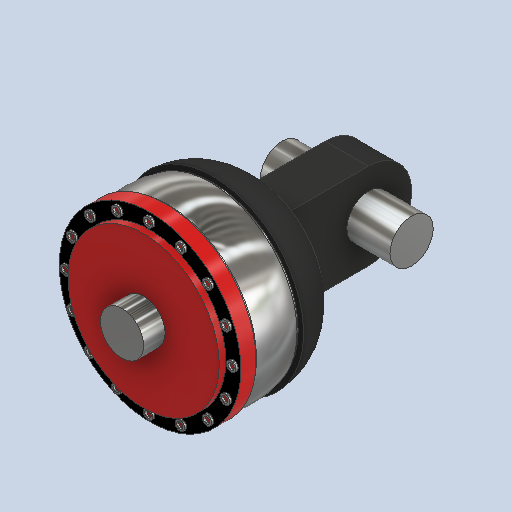
# Autodesk Inventor part: 6
Saved by Autodesk Inventor 2027.1 (Build 311270010, 270A)
## iProperties
Part Number: 6
Material: Allgemein
Document SubType Name: Modellieren
Designer: Asus
Appearance: Chrom - poliert
Author: Asus
Autodesk Inventor part; units mm, degrees
ref_plane "YZ-Ebene" through (0, 0, 0) normal (1, 0, 0) x (0, 1, 0)
ref_plane "XZ-Ebene" through (0, 0, 0) normal (0, 1, 0) x (-1, 0, 0)
sketch "Skizze1" plane through (0, 0, 0) normal (0, 0, 1) x (1, 0, 0)
  line L0 (0, 0) -> (20, 0)
  line L1 (0, 0) -> (0, -42)
  line L2 (20, 0) -> (20, -31)
  arc A0 (0, -42) -> (20, -31) centre (-0.7193, -17.0104) ccw
  dimension "d0" = 20
  dimension "d1" = 42
  dimension "d2" = 31
  dimension "d3" = 25
  constraints: 6 end point, 2 point on circle, 2 vertical, 1 centre point, 1 horizontal
  measures "d0" distance of L0.start L0.end
  measures "d1" distance of L0.start L1.end
  measures "d2" distance of L0.end L2.end
  measures "d3" radius of A0
revolve "Umdrehung1" add sketch "Skizze1" angle 360 about axis through (0, 0, 0) along (1, 0, 0)
sketch "Skizze2" plane through (0, 0, 0) normal (-1, 0, 0) x (0, 0, 1)
  circle A0 centre (0, 0) radius 39.5
  dimension "d5" = 79
  constraints: 1 centre point, 1 coincident
  measures "d5" diameter of A0
extrude "Extrusion1" add sketch "Skizze2" along normal blind 1
sketch "Skizze3" plane through (0, 0, 0) normal (0, 1, 0) x (-1, 0, 0)
  line L0 (1, -39.5) -> (0, -39.5) construction
  line L1 (0, -39.5) -> (0, -42) construction
  arc A0 (-20, -31) -> (0, -42) centre (0.7193, -17.0104) ccw construction
  line L2 (-20, -31) -> (-20, 31) construction
  arc A1 (0, 42) -> (-20, 31) centre (0.7193, 17.0104) ccw construction
  line L3 (0, 42) -> (0, 39.5) construction
  line L4 (0, 39.5) -> (1, 39.5) construction
  line L5 (1, 39.5) -> (1, -39.5) construction
  line L6 (1, 0) -> (21, 0)
  line L7 (1, 0) -> (1, 40)
  line L8 (21, 0) -> (21, 40)
  arc A2 (21, 40) -> (1, 40) centre (11, 4.377) ccw
  point P0 (0, 0)
  dimension "d8" = 20
  dimension "d9" = 40
  dimension "d10" = 40
  dimension "d11" = 37
  constraints: 6 end point, 2 point on circle, 1 centre point, 1 horizontal, 1 midpoint, 1 point on line, 1 vertical
  measures "d8" distance of L6.start L6.end
  measures "d9" distance of L6.start L7.end
  measures "d10" distance of L6.end L8.end
  measures "d11" radius of A2
revolve "Umdrehung2" add sketch "Skizze3" angle 360 about axis through (-1, 0, 0) along (-1, 0, 0)
sketch "Skizze4" plane through (-21, 0, 0) normal (-1, 0, 0) x (0, 0, 1)
  circle A0 centre (0, 0) radius 41.25
  dimension "d13" = 82.5
  constraints: 1 centre point, 1 coincident
  measures "d13" diameter of A0
extrude "Extrusion2" add sketch "Skizze4" along normal blind 1
sketch "Skizze5" plane through (-22, 0, 0) normal (-1, 0, 0) x (0, 0, 1)
  circle A0 centre (0, 0) radius 42
  dimension "d16" = 84
  constraints: 1 centre point, 1 coincident
  measures "d16" diameter of A0
extrude "Extrusion3" add sketch "Skizze5" along normal blind 7
sketch "Skizze6" plane through (-29, 0, 0) normal (-1, 0, 0) x (0, 0, 1)
  circle A0 centre (0, 0) radius 35
  dimension "d19" = 70
  constraints: 1 centre point, 1 coincident
  measures "d19" diameter of A0
extrude "Extrusion4" add sketch "Skizze6" along normal blind 3
sketch "Skizze7" plane through (-29, 0, 0) normal (-1, 0, 0) x (0, 0, 1)
  circle A0 centre (0, 0) radius 35 construction
  circle A1 centre (0, 0) radius 42 construction
  circle A2 centre (-38.5, 0) radius 2.25
  circle A3 centre (-38.5, 0) radius 1.5
  dimension "d22" = 4.5
  dimension "d23" = 3
  dimension "d24" = 38.5
  constraints: 2 centre point, 1 coincident, 1 horizontal alignment
  measures "d22" diameter of A2
  measures "d23" diameter of A3
  measures "d24" distance of point (0, 0) A2.centre
extrude "Extrusion5" add sketch "Skizze7" along normal blind 1
pattern_circular "Runde Anordnung1" count 16 over 360 about axis through (-29, 0, 0) along (-1, 0, 0) of "Extrusion5"
sketch "Skizze8" plane through (20, 0, 0) normal (1, 0, 0) x (0, 0, -1)
  line L0 (-10, -20) -> (10, -20)
  line L1 (10, -20) -> (10, 20)
  line L2 (10, 20) -> (-10, 20)
  line L3 (-10, 20) -> (-10, -20)
  line L4 (-10, -20) -> (10, 20) construction
  line L5 (10, -20) -> (-10, 20) construction
  point P0 (0, 0)
  dimension "d30" = 20
  dimension "d31" = 40
  constraints: 12 end point, 2 midpoint, 2 parallel, 1 horizontal, 1 perpendicular
  measures "d30" distance of L2.end L1.end
  measures "d31" distance of L1.end L0.end
extrude "Extrusion6" add sketch "Skizze8" along normal blind 42
sketch "Skizze9" plane through (20, -20, 10) normal (0, 0, 1) x (1, 0, 0)
  line L0 (0, 0) -> (0, 40) construction
  line L1 (0, 0) -> (42, 0) construction
  line L2 (42, 40) -> (42, 0) construction
  line L3 (0, 40) -> (42, 40) construction
  circle A0 centre (42, 20) radius 20
  point P0 (-20, 20)
  dimension "d34" = 40
  constraints: 1 centre point, 1 midpoint
  measures "d34" diameter of A0
extrude "Extrusion7" add sketch "Skizze9" against normal blind 20
sketch "Skizze10" plane through (20, -20, -10) normal (0, 0, -1) x (-1, 0, 0)
  arc A0 (-42, 40) -> (-42, 0) centre (-42, 20) ccw projected
  circle A1 centre (-42, 20) radius 10
  point P0 (20, 20)
  dimension "d37" = 20
  constraints: 1 centre point, 1 coincident
  measures "d37" diameter of A1
extrude "Extrusion8" add sketch "Skizze10" along normal blind 10
sketch "Skizze11" plane through (-32, 0, 0) normal (-1, 0, 0) x (0, 0, 1)
  circle A0 centre (0, 0) radius 10
  dimension "d40" = 20
  constraints: 1 centre point, 1 coincident
  measures "d40" diameter of A0
extrude "Extrusion9" add sketch "Skizze11" along normal blind 10
ref_plane "Arbeitsebene1" through (20, -20, 0) normal (0, 0, -1) x (-1, 0, 0)
mirror "Spiegeln1" about plane through (20, -20, 0) normal (0, 0, -1) of "Extrusion8"
sketch "Skizze12" plane through (62, 0, 20) normal (0, 0, 1) x (1, 0, 0)
  circle A0 centre (0, 0) radius 10 projected
  point P0 (-62, 0)
extrude "Extrusion10" add sketch "Skizze12" along normal blind 10
mirror "Spiegeln2" about plane through (20, -20, 0) normal (0, 0, -1) of "Extrusion10"
